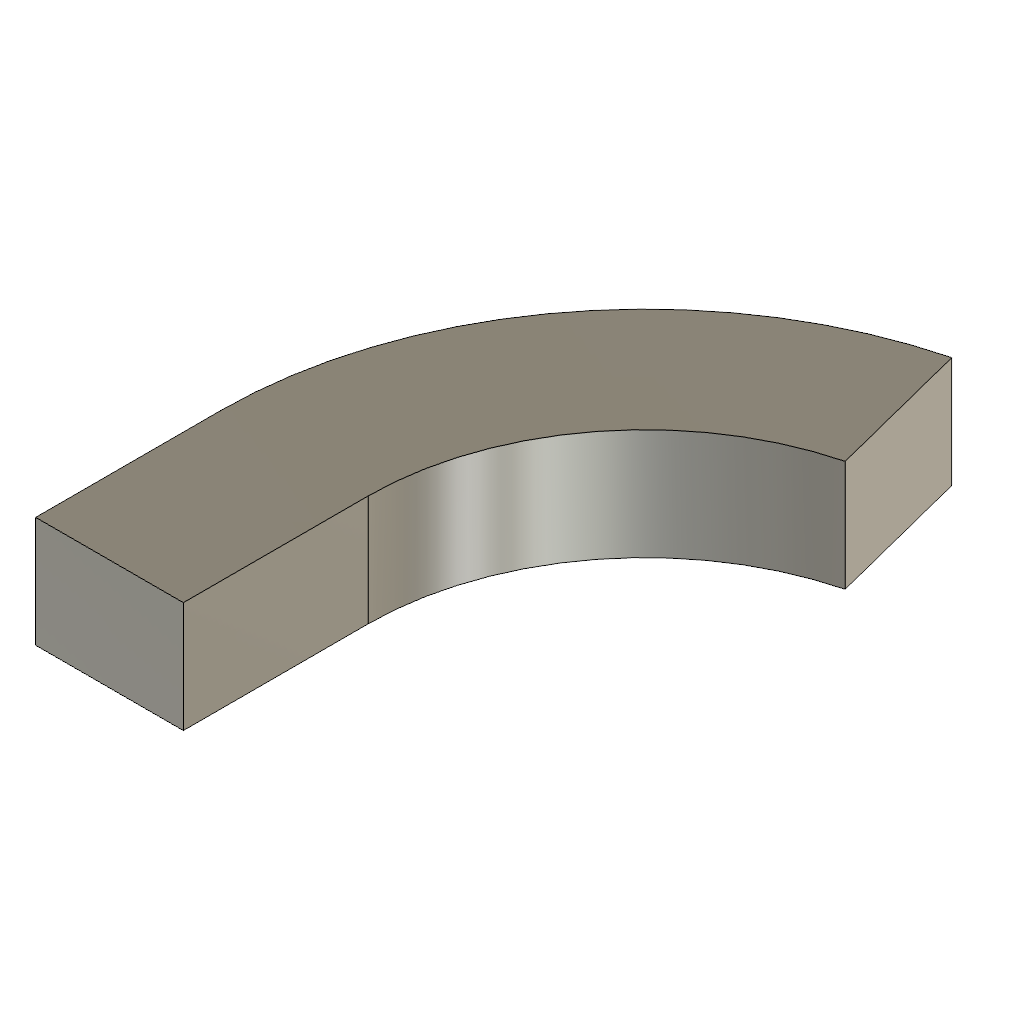
vendor_SweepSCurve (Autodesk Fusion 360 design; units mm, degrees)
Autodesk Fusion 360 part; units mm, degrees
sketch "Bar profile" plane through (0, 0, 0) normal (0, 1, 0) x (1, 0, 0)
  line L0 (-3, -2) -> (5, -2)
  line L1 (5, -2) -> (5, -8)
  line L2 (5, -8) -> (-3, -8)
  line L3 (-3, -8) -> (-3, -2)
sketch "Bar path" plane through (0, 0, 0) normal (0, 0, 1) x (1, 0, 0)
  line L0 (0, 0) -> (0, 10)
  arc A0 (20, 30) -> (0, 10) centre (20, 10) ccw
  arc A1 (20, 30) -> (40, 50) centre (20, 50) ccw
sweep "Bar sweep" add profiles "Bar profile" path "Bar path" along L0 A0 A1 for 0.5 of its length starting at (0, 0, 0) heading (0, 1, 0) section 1
equation "height = 20.0 mm"
